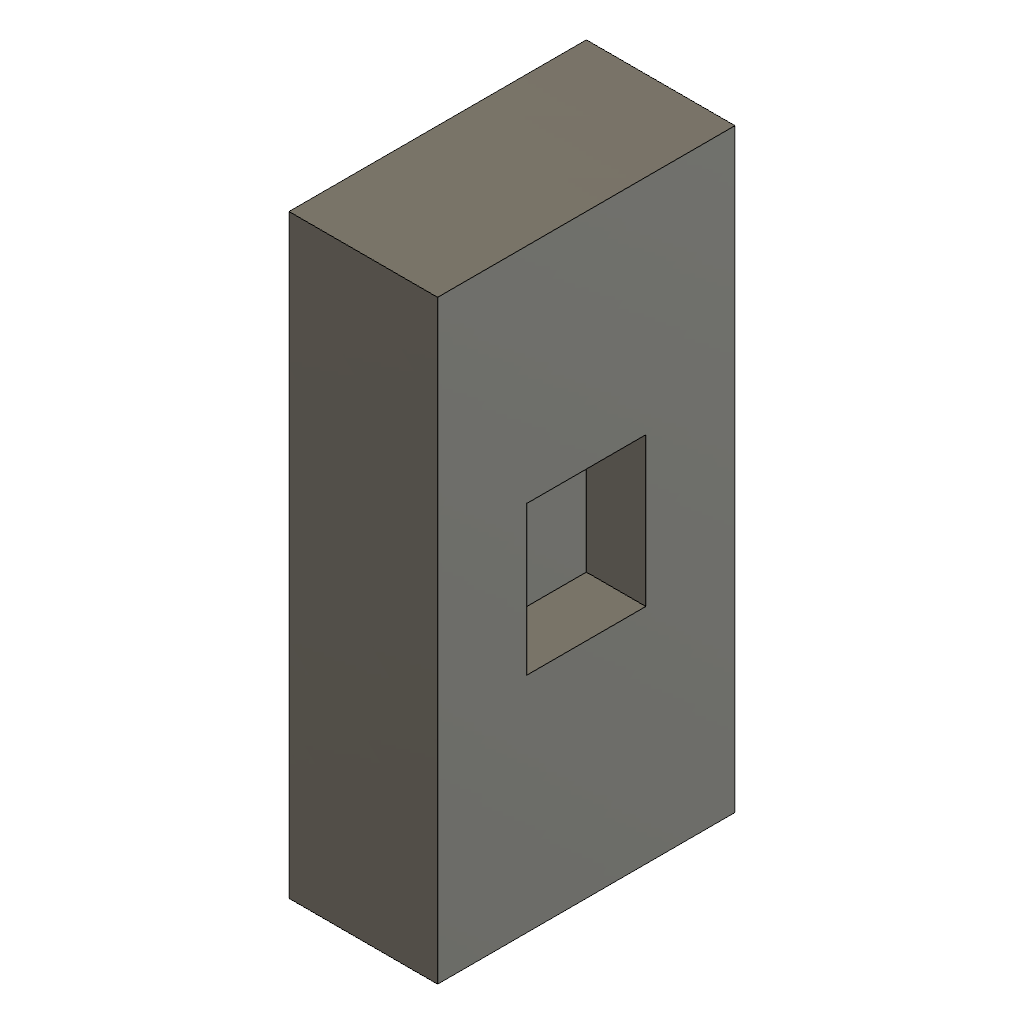
P04-fusion-plane-yz (Autodesk Fusion 360 design; units mm, degrees)
part number: 2026-11-14-20-03-21-053
Autodesk Fusion 360 part; units mm, degrees
sketch "RectangleSketch" plane through (0, 0, 0) normal (1, 0, 0) x (0, 0, -1)
  line L0 (0, 0) -> (0, 40)
  line L1 (0, 40) -> (-20, 40)
  line L2 (-20, 40) -> (-20, 0)
  line L3 (-20, 0) -> (0, 0)
  dimension "width_mm" = 40
  dimension "height_mm" = 20
  constraint vertical L0
  constraint horizontal L1
  constraint vertical L2
  constraint horizontal L3
  constraint coincident L0.start L3.end
  measures "width_mm" vertical distance of L0.start L0.end
  measures "height_mm" horizontal distance of L0.start L2.end
extrude "BlindBoss" add sketch "RectangleSketch" along normal blind 10
sketch "CutSketch" plane through (10, 0, 0) normal (1, 0, 0) x (0, 0, -1)
  line L0 (-20, 0) -> (0, 0)
  line L1 (0, 0) -> (0, 40)
  line L2 (0, 40) -> (-20, 40)
  line L3 (-20, 40) -> (-20, 0)
  line L4 (-6, 15) -> (-6, 25)
  line L5 (-6, 25) -> (-14, 25)
  line L6 (-14, 25) -> (-14, 15)
  line L7 (-14, 15) -> (-6, 15)
  line L8 (-6, 15) -> (-14, 25) construction
  point P0 (-10, 20)
  dimension "cut_width_mm" = 10
  dimension "cut_height_mm" = 8
  dimension "cut_center_u_mm" = 20
  dimension "cut_center_v_mm" = 10
  constraint vertical L4
  constraint horizontal L5
  constraint vertical L6
  constraint horizontal L7
  constraint midpoint L8 P0
  measures "cut_width_mm" vertical distance of L4.start L4.end
  measures "cut_height_mm" horizontal distance of L4.start L6.end
  measures "cut_center_u_mm" vertical distance of P0 L0.end
  measures "cut_center_v_mm" horizontal distance of P0 L0.end
extrude "BlindCut" cut sketch "CutSketch" against normal blind 4 contours L4 L5 L6 L7
equation "depth_mm = 10 mm"
equation "cut_center_u_mm = width_mm / 2"
equation "cut_center_v_mm = height_mm / 2"
equation "cut_depth_mm = -( 4 mm )"
